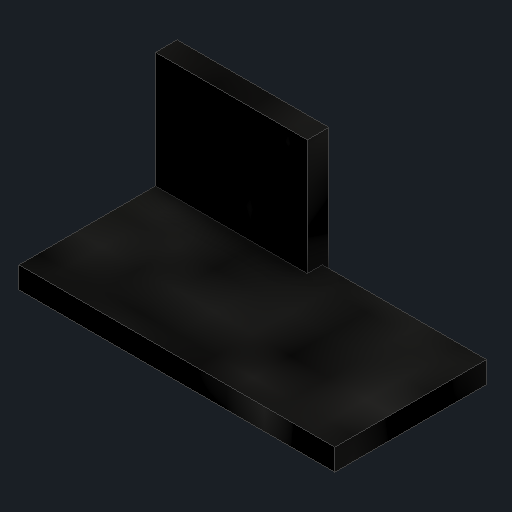
# Autodesk Inventor part: usb_cable_compact
Saved by Autodesk Inventor 2027.1 (Build 311270010, 270A)
## iProperties
Created: 2026-10-29
Part Number: usb_cable_compact
Material: Generic
Document SubType Name: Modeling
Designer: alexg
Density: 1 g/cm^3
Appearance: Smooth - Black
Description: USB flat ribbon (schematic) from the Pi plug to the raised v2 panel socket
Mass: 0.14147 g
Surface Area: 3.3736 cm^2
Volume: 0.14147 cm^3
Author: alexg
Autodesk Inventor part; units mm, degrees
ref_plane "Work Plane1" through (0, -26.34, 0) normal (0, 1, 0) x (-1, 0, 0)
sketch "Run along Pi edge sketch" plane through (0, -26.34, 0) normal (0, 1, 0) x (-1, 0, 0)
  line L0 (27.5, -12.5) -> (12.93, -12.5)
  line L1 (12.93, -12.5) -> (12.93, -5.5)
  line L2 (12.93, -5.5) -> (27.5, -5.5)
  line L3 (27.5, -5.5) -> (27.5, -12.5)
  constraints: 8 end point, 2 parallel, 1 horizontal, 1 perpendicular
extrude "Run along Pi edge" add sketch "Run along Pi edge sketch" along normal blind 1
ref_plane "Work Plane2" through (0, -26.34, 0) normal (0, 1, 0) x (-1, 0, 0)
sketch "Fold into socket sketch" plane through (0, -26.34, 0) normal (0, 1, 0) x (-1, 0, 0)
  line L0 (27.5, -12.8) -> (20.5, -12.8)
  line L1 (20.5, -12.8) -> (20.5, -12.5)
  line L2 (20.5, -12.5) -> (27.5, -12.5)
  line L3 (27.5, -12.5) -> (27.5, -12.8)
  constraints: 8 end point, 2 parallel, 1 horizontal, 1 perpendicular
extrude "Fold into socket" add sketch "Fold into socket sketch" along normal blind 1
ref_plane "Work Plane3" through (0, 0, -12.8) normal (0, 0, 1) x (1, 0, 0)
sketch "Riser up to the raised socket (+5.34) sketch" plane through (0, 0, -12.8) normal (0, 0, 1) x (1, 0, 0)
  line L0 (-27.5, -26.34) -> (-20.5, -26.34)
  line L1 (-20.5, -26.34) -> (-20.5, -20)
  line L2 (-20.5, -20) -> (-27.5, -20)
  line L3 (-27.5, -20) -> (-27.5, -26.34)
  constraints: 8 end point, 2 parallel, 1 horizontal, 1 perpendicular
extrude "Riser up to the raised socket (+5.34)" add sketch "Riser up to the raised socket (+5.34) sketch" along normal blind 1
body "Solid1"
